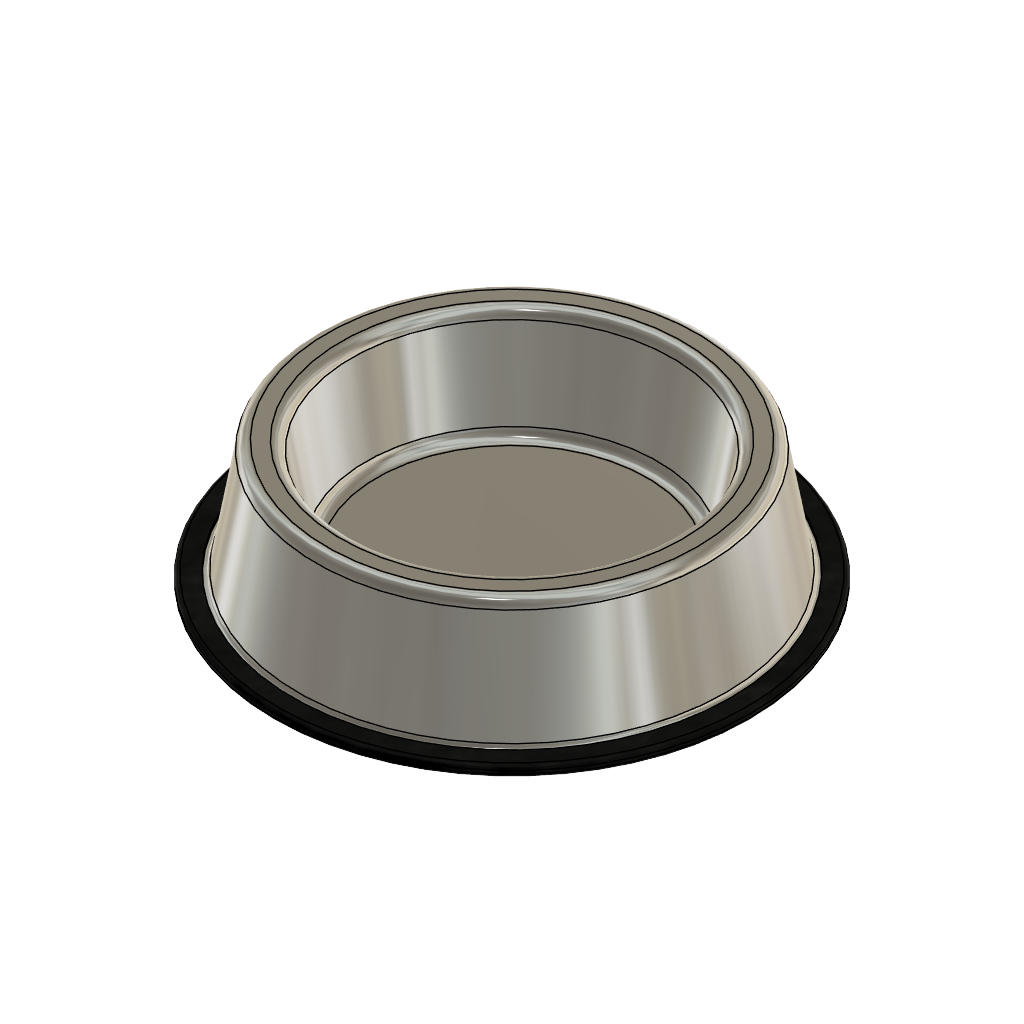
Day10-DogBowl (Autodesk Fusion 360 design; units mm, degrees)
part number: 2026-10-27-23-31-22-175
part number: 2026-10-27-23-38-11-772
part number: 2026-10-27-23-39-17-302
Autodesk Fusion 360 part; units mm, degrees
sketch "Sketch1" plane through (0, 0, 0) normal (0, 1, 0) x (1, 0, 0) in component "metal bowl"
  line L0 (0, 0) -> (110, 0) construction
  line L1 (110, 0) -> (110, -2.5)
  line L2 (110, -2.5) -> (100, -2.5)
  line L3 (100, -2.5) -> (90.4494, -56.6644)
  line L4 (90.4494, -56.6644) -> (75.4494, -56.6644)
  line L5 (75.4494, -56.6644) -> (67.2212, -10)
  line L6 (0, -10) -> (67.2212, -10)
  dimension "d1" = 110
  dimension "d2" = 2.5
  dimension "d3" = 10
  dimension "d4" = 100
  dimension "d5" = 55
  dimension "d6" = 15
  dimension "d7" = 10
  dimension "d8" = 100
  constraint coincident L0.start origin
  constraint horizontal L0
  constraint perpendicular L0 L1
  constraint perpendicular L1 L2
  constraint parallel L0 L4
  constraint horizontal L6
  constraint vertical L0.start L6.start
  measures "d1" distance of L0.start L0.end
  measures "d2" distance of L0.end L1.end
  measures "d3" distance of L1.end L2.end
  measures "d4" angle of L2 L3
  measures "d5" distance of L2.end L3.end
  measures "d6" distance of L3.end L4.end
  measures "d7" distance of L0 L6
  measures "d8" angle of L5 L6
surface "Revolve1" add revolved angle 360 about axis through (0, 0, 1.75) along (0, 0, 20.75) path "Sketch1" along L1 L2 L3 L4 L5 L6 makes body 1 in component "metal bowl"
fillet "Fillet1" radius 5 3 edges at (-84.3284, -32.7079, 56.6644) (-70.3435, -27.2836, 56.6644) (-62.6721, -24.3082, 10) on bodies 1 in component "metal bowl"
fillet "Fillet1" radius 2.5 1 edges at (-93.2327, -36.1615, 2.5) on bodies 1 in component "metal bowl"
thicken "Thicken1" add thickness -2.5 9 faces at (95.7351, 14.4297, 20.5548) (-15.4183, 87.4414, 55.9733) (83.7297, -4.2852, 56.6644) (-73.1765, -30.8465, 56.659) (36.2319, -62.7555, 39.7324) (-18.337, -65.1734, 13.2353) (-4.6748, 20.4818, 10) (-76.4529, 64.1516, 4.0098) (106.9564, -5.4649, 2.5) separate body on bodies 1 makes body 2 in component "metal bowl"
fillet "Fillet2" radius 0.5 2 edges at (-102.556, -39.7777, 2.5) (-102.556, -39.7777, 0) on bodies 2 in component "metal bowl"
offset_surface "SurfaceOffset1" offset 0.3 5 faces at (106.6249, -5.44, 0) (87.6312, 66.378, 0.25) (19.1013, -108.3289, 1) (-13.6695, -109.0798, 2.25) (106.6249, -5.44, 2.5) on bodies 2 makes body 3 in component "rubber grip"
thicken "Thicken1'" add thickness 1 5 faces at (106.6249, -5.44, 2.8) (50.2711, -98.0575, 2.4) (-29.8737, -106.1775, 1) (87.8383, 66.5349, 0.1) (106.6249, -5.44, -0.3) separate body on bodies 3 makes body 4 in component "rubber grip"
component "metal bowl" placed x (1, 0, 0) y (0, 1, 0) z (0, 0, 1) at (0, 0, 0)
component "rubber grip" placed x (1, 0, 0) y (0, 1, 0) z (0, 0, 1) at (0, 0, 0)
hidden bodies 1 3
